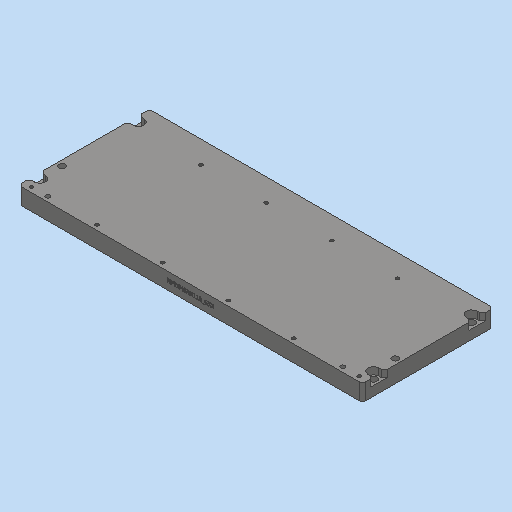
# Autodesk Inventor part: MM0948AN110_G01_100
Saved by Autodesk Inventor 2023.3 (Build 273359000, 359)
## iProperties
Part Number: MM0948AN110_G01_100
Material: 1.2099 X5CrS12
Description: =<RBPARTNOTITLE2>
Document SubType Name: Modeling
Designer: Benutzer
Mass: 35205.2 g
Surface Area: 3659.45 cm^2
Volume: 4484.74 cm^3
Density: 7.85 g/cm^3
Appearance: Stahl - rostfrei AnP
Created: 2023-03-23
RBDOCUMENTTYPE: DRF
RBDOCUMENTVERSION: 00
RBDRAWINGMAINSCALE: 1:1
RBDRAWINGMISSINGSPEC: --
RBDRAWINGVOLUME: --
RBGBEDGESIN1: +0,5
RBGBEDGESIN2: +0,2
RBGBEDGESOUT1: -0,3
RBGBEDGESOUT2: -0,1
RBMATERIAL: =<Material>
RBMATMEETS: --
RBMATNO: =<Part Number>
RBPARTMADEOF: 30 x 240 x 630 (FM)
RBPARTNO: SIEHE MNR
RBPARTNOTITLE1: manufactured part
RBPARTNOTITLE2: Anfertigungsteil
RBPARTSAFETYINDICATOR: --
RBSURFACE: --
RBSURFACE2: --
RBZEDGESNORM: ISO13715:2002-06
RBZGENDIMCLASS: m
RBZGENDIMNORM: ISO 2768-1:1989-11
RBZGENGEOCLASS: H
RBZGENGEONORM: ISO 2768-2:1989-11
RBZSURFACENORM: ISO13D2:2002-02
RBZTOLERANCENORM: ISO 14405-1:2010-12
AnP_Material: =<Material>
AnP_TemplVers: 20190222
AnP_Kategorie: 1
MaxAbmaße: 30 x 240 x 630 (FM)
AnP_Kommentar_aktuell: =<Comments>
AnP_Material_aktuell: =<Material>
Author: FH/Wi
Keywords: =<RBPARTMADEOF>
Comments: =<RBSURFACE2>
Revision Number: 01
Autodesk Inventor part; units mm, degrees
ref_plane "YZ Plane" through (0, 0, 0) normal (1, 0, 0) x (0, 1, 0)
ref_plane "XZ Plane" through (0, 0, 0) normal (0, 1, 0) x (-1, 0, 0)
ref_plane "XY Plane" through (0, 0, 0) normal (0, 0, 1) x (1, 0, 0)
sketch "Skizze1" plane through (0, 0, 0) normal (0, 0, 1) x (1, 0, 0)
  line L0 (-315, 240) -> (315, 240)
  line L1 (315, 240) -> (315, 0)
  line L2 (315, 0) -> (-315, 0)
  line L3 (-315, 0) -> (-315, 240)
  point P0 (0, 0)
  point P1 (0, 0)
  dimension "d0" = 240
  dimension "d1" = 630
  constraints: 8 end point, 2 parallel, 1 coincident, 1 horizontal, 1 midpoint, 1 perpendicular
  measures "d0" distance of L2.end L0.start
  measures "d1" distance of L0.start L0.end
extrude "Extrusion1" add sketch "Skizze1" along normal blind 30
sketch "Skizze2" plane through (0, 0, 30) normal (0, 0, 1) x (1, 0, 0)
  line L0 (-305, 210) -> (305, 210) construction
  line L1 (305, 210) -> (305, 30) construction
  line L2 (305, 30) -> (-305, 30) construction
  line L3 (-305, 30) -> (-305, 210) construction
  line L4 (315, 240) -> (-315, 240) construction
  line L5 (-315, 0) -> (315, 0) construction
  line L6 (-305, -150) -> (305, -150) construction
  line L7 (305, -150) -> (305, -330) construction
  line L8 (305, -330) -> (-305, -330) construction
  line L9 (-305, -330) -> (-305, -150) construction
  point P0 (0, 0)
  point P1 (0, 0)
  point P2 (0, 30)
  dimension "d4" = 610
  dimension "d5" = 30
  dimension "d6" = 180
  dimension "d19" = 180
  dimension "d20" = 180
  constraints: 16 end point, 8 coincident, 4 parallel, 3 vertical alignment, 2 horizontal, 2 midpoint, 2 perpendicular
  measures "d4" distance of L0.start L0.end
  measures "d5" distance between parallel lines of L0 L4
  measures "d6" distance of L2.end L0.start
  measures "d19" distance between parallel lines of L2 L6
  measures "d20" distance of L8.end L6.start
hole "Bohrung1" at (-305, 210, 30) at (305, 210, 30) at (-305, 30, 30) at (305, 30, 30) at (-305, -150, 30) at (-305, -330, 30) at (305, -330, 30) at (305, -150, 30) direction (0, 0, -1) diameter 13.5 end through all counterbore diameter 20 counterbore depth 13 clearance for "Inbusschraube ISO 4762  versenkt" size "M12" standard "ISO"
sketch "Skizze3" plane through (0, 0, 30) normal (0, 0, 1) x (1, 0, 0)
  line L0 (315, 240) -> (-315, 240) projected
  line L1 (-315, 240) -> (-315, 210) projected
  circle A0 centre (-305, 210) radius 10 projected
  line L2 (-315, 210) -> (-315, 30) projected
  circle A1 centre (-305, 30) radius 10 projected
  line L3 (-315, 30) -> (-315, 0) projected
  line L4 (-315, 0) -> (315, 0) projected
  line L5 (315, 0) -> (315, 30) projected
  circle A2 centre (305, 30) radius 10 projected
  line L6 (315, 30) -> (315, 210) projected
  circle A3 centre (305, 210) radius 10 projected
  line L7 (315, 210) -> (315, 240) projected
  line L8 (-305, 220) -> (-315, 220)
  line L9 (-315, 220) -> (-315, 200)
  line L10 (-315, 200) -> (-305, 200)
  line L11 (-305, 200) -> (-305, 220)
  line L12 (-305, 40) -> (-315, 40)
  line L13 (-315, 40) -> (-315, 20)
  line L14 (-315, 20) -> (-305, 20)
  line L15 (-305, 20) -> (-305, 40)
  line L16 (305, 40) -> (315, 40)
  line L17 (315, 40) -> (315, 20)
  line L18 (315, 20) -> (305, 20)
  line L19 (305, 20) -> (305, 40)
  line L20 (305, 220) -> (315, 220)
  line L21 (315, 220) -> (315, 200)
  line L22 (315, 200) -> (305, 200)
  line L23 (305, 200) -> (305, 220)
  circle A4 centre (-305, 210) radius 10 projected
  line L24 (315, 30) -> (315, 210) projected
  line L25 (-315, 30) -> (-315, 0) projected
  line L26 (-315, 210) -> (-315, 30) projected
  line L27 (315, 0) -> (315, 240) projected
  point P0 (315, 30)
  point P1 (305, 30)
  constraints: 32 end point, 8 parallel, 5 horizontal, 4 collinear, 4 perpendicular, 4 point on circle, 4 tangent, 3 point on line, 1 horizontal alignment
extrude "Extrusion2" cut sketch "Skizze3" against normal up to surface (13 mm away) contours L7 A3 L20 | L8 A0 L1 | A3 L23 | L6 L22 A3 | A0 L11 | A0 L10 L2 | L6 A2 L16 | L12 A1 L2 | A2 L19 | L5 L18 A2 | A1 L15 | A1 L14 L3 picked at (306.4463, 213.0032) picked at (-306.4463, 206.9968) picked at (307.6061, 27.9217) picked at (-307.6061, 27.9217)
chamfer "Fase1" distance 5 angle 45 12 edges at (315, 0, 15) (315, 240, 15) (-315, 0, 15) (-315, 240, 15) (-315, 220, 23.5) (-315, 200, 23.5) (-315, 40, 23.5) (-315, 20, 23.5) (315, 20, 23.5) (315, 40, 23.5) (315, 200, 23.5) (315, 220, 23.5)
sketch "Skizze4" plane through (0, 0, 30) normal (0, 0, 1) x (1, 0, 0)
  circle A0 centre (-305, 210) radius 6.75 projected
  circle A1 centre (305, 210) radius 6.75 projected
  point P0 (0, 0)
  point P1 (-305, 170)
  point P2 (305, 170)
  dimension "d21" = 40
  dimension "d22" = 40
  constraints: 2 vertical alignment
  measures "d21" distance of A0.centre point (-305, 170)
  measures "d22" distance of point (305, 170) A1.centre
hole "Bohrung2" at (-305, 170, 30) at (305, 170, 30) direction (0, 0, -1) diameter 12 end through all
sketch "Skizze8" plane through (0, 0, 30) normal (0, 0, 1) x (1, 0, 0)
  line L0 (310, 240) -> (-310, 240) projected
  line L1 (0, 288) -> (0, -48) projected
  line L2 (-441, 0) -> (441, 0) projected
  point P0 (0, 0)
  point P1 (180, 231)
  point P2 (60, 231)
  point P3 (-60, 231)
  point P4 (-180, 231)
  point P5 (-180, 41)
  point P6 (-60, 41)
  point P7 (60, 41)
  point P8 (180, 41)
  point P9 (300, 231)
  point P10 (-300, 231)
  dimension "d59" = 120
  dimension "d60" = 120
  dimension "d61" = 120
  dimension "d62" = 190
  dimension "d63" = 9
  dimension "d89" = 60
  dimension "d94" = 120
  dimension "d95" = 120
  constraints: 8 horizontal alignment, 4 vertical alignment
  measures "d59" distance of point (60, 41) point (180, 41)
  measures "d60" distance of point (-60, 41) point (60, 41)
  measures "d61" distance of point (-180, 41) point (-60, 41)
  measures "d62" distance of point (180, 231) point (180, 41)
  measures "d63" distance from line of point (180, 231) L0
  measures "d89" distance from line of L1 point (-60, 231)
  measures "d94" distance of point (180, 231) point (300, 231)
  measures "d95" distance of point (-300, 231) point (-180, 231)
hole "Bohrung6" at (180, 231, 30) at (60, 231, 30) at (-60, 231, 30) at (-180, 231, 30) at (-180, 41, 30) at (-60, 41, 30) at (60, 41, 30) at (180, 41, 30) at (300, 231, 30) at (-300, 231, 30) direction (0, 0, -1) diameter 6.647 end through all thread size "M8x1.25" designation "M8" class "6H" standard "ISO Metric profile"
sketch "Skizze9" plane through (0, 0, 30) normal (0, 0, 1) x (1, 0, 0)
  circle A0 centre (180, 231) radius 3.3235 projected
  line L0 (0, 288) -> (0, -48) projected
  point P0 (0, 0)
  point P1 (270, 231)
  point P2 (-270, 231)
  dimension "d71" = 0
  dimension "d72" = 540
  dimension "d90" = 90
  constraints: 1 horizontal alignment
  measures "d71" vertical distance of point (-270, 231) point (270, 231)
  measures "d72" distance of point (-270, 231) point (270, 231)
  measures "d90" distance of point (270, 231) A0.centre
hole "Bohrung7" at (270, 231, 30) at (-270, 231, 30) direction (0, 0, -1) diameter 7.8 end through all counterbore diameter 8 counterbore depth 15
sketch "Skizze11" plane through (-310, 240, 0) normal (0, 1, 0) x (1, 0, 0)
  line L0 (528.1373, -4.1156) -> (91.8627, -4.1156) construction
  line L1 (91.8627, -4.1156) -> (91.8627, -25.8844) construction
  line L2 (91.8627, -25.8844) -> (528.1373, -25.8844) construction
  line L3 (528.1373, -25.8844) -> (528.1373, -4.1156) construction
  line L4 (620, -30) -> (0, -30) projected
  line L5 (620, 0) -> (620, -30) projected
  line L6 (0, 0) -> (620, 0) projected
  line L7 (346.6224, -12.124) -> (347.5527, -12.124)
  line L8 (347.5527, -12.124) -> (347.5527, -18.154)
  line L9 (347.5527, -18.154) -> (349.3793, -14.0527)
  line L10 (349.3793, -14.0527) -> (349.9465, -14.0527)
  line L11 (349.9465, -14.0527) -> (351.7561, -18.154)
  line L12 (351.7561, -18.154) -> (351.7561, -12.124)
  line L13 (351.7561, -12.124) -> (352.624, -12.124)
  line L14 (352.624, -12.124) -> (352.624, -19.124)
  line L15 (352.624, -19.124) -> (351.3533, -19.124)
  line L16 (351.3533, -19.124) -> (349.6062, -15.2269)
  line L17 (349.6062, -15.2269) -> (347.9157, -19.124)
  line L18 (347.9157, -19.124) -> (346.6224, -19.124)
  line L19 (346.6224, -19.124) -> (346.6224, -12.124)
  line L20 (339.2026, -12.124) -> (340.1329, -12.124)
  line L21 (340.1329, -12.124) -> (340.1329, -18.154)
  line L22 (340.1329, -18.154) -> (341.9595, -14.0527)
  line L23 (341.9595, -14.0527) -> (342.5267, -14.0527)
  line L24 (342.5267, -14.0527) -> (344.3363, -18.154)
  line L25 (344.3363, -18.154) -> (344.3363, -12.124)
  line L26 (344.3363, -12.124) -> (345.2042, -12.124)
  line L27 (345.2042, -12.124) -> (345.2042, -19.124)
  line L28 (345.2042, -19.124) -> (343.9335, -19.124)
  line L29 (343.9335, -19.124) -> (342.1864, -15.2269)
  line L30 (342.1864, -15.2269) -> (340.4959, -19.124)
  line L31 (340.4959, -19.124) -> (339.2026, -19.124)
  line L32 (339.2026, -19.124) -> (339.2026, -12.124)
  spline S0 degree 2 poles (333.6264, -15.624) (333.6264, -13.7407) (334.7212, -11.9765) (335.8614, -11.9765) knots 0 0 0 1 2 2 2
  spline S1 degree 2 poles (335.8614, -11.9765) (337.0186, -11.9765) (338.1021, -13.7747) (338.1021, -15.6183) knots 0 0 0 1 2 2 2
  spline S2 degree 2 poles (338.1021, -15.6183) (338.1021, -17.513) (337.0073, -19.2658) (335.8614, -19.2658) knots 0 0 0 1 2 2 2
  spline S3 degree 2 poles (335.8614, -19.2658) (334.7099, -19.2658) (333.6264, -17.4506) (333.6264, -15.624) knots 0 0 0 1 2 2 2
  spline S4 degree 2 poles (334.829, -13.4911) (334.6929, -13.8371) (334.5794, -14.9036) (334.5794, -15.624) knots 0 0 0 1 2 2 2
  spline S5 degree 2 poles (334.5794, -15.624) (334.5794, -16.3444) (334.6929, -17.4052) (334.8347, -17.7626) knots 0 0 0 1 2 2 2
  spline S6 degree 2 poles (334.8347, -17.7626) (334.9765, -18.1199) (335.47, -18.4887) (335.8614, -18.4887) knots 0 0 0 1 2 2 2
  spline S7 degree 2 poles (335.8614, -18.4887) (336.2528, -18.4887) (336.7577, -18.1199) (336.9052, -17.7512) knots 0 0 0 1 2 2 2
  spline S8 degree 2 poles (336.9052, -17.7512) (337.047, -17.3938) (337.1491, -16.3047) (337.1491, -15.6183) knots 0 0 0 1 2 2 2
  spline S9 degree 2 poles (337.1491, -15.6183) (337.1491, -14.8809) (337.0583, -13.8938) (336.9109, -13.5081) knots 0 0 0 1 2 2 2
  spline S10 degree 2 poles (336.9109, -13.5081) (336.7747, -13.1451) (336.2699, -12.7536) (335.8614, -12.7536) knots 0 0 0 1 2 2 2
  spline S11 degree 2 poles (335.8614, -12.7536) (335.4757, -12.7536) (334.9708, -13.1224) (334.829, -13.4911) knots 0 0 0 1 2 2 2
  spline S12 degree 2 poles (332.923, -16.8493) (332.923, -17.3882) (332.5713, -18.2844) (332.265, -18.6078) knots 0 0 0 1 2 2 2
  spline S13 degree 2 poles (332.265, -18.6078) (331.9757, -18.9198) (331.1305, -19.2658) (330.6994, -19.2658) knots 0 0 0 1 2 2 2
  spline S14 degree 2 poles (330.6994, -19.2658) (330.2172, -19.2658) (329.4344, -18.9425) (329.1451, -18.6361) knots 0 0 0 1 2 2 2
  spline S15 degree 2 poles (329.1451, -18.6361) (328.782, -18.2504) (328.3849, -17.0024) (328.3849, -16.0438) knots 0 0 0 1 2 2 2
  spline S16 degree 2 poles (328.3849, -16.0438) (328.3849, -15.1759) (328.7763, -13.6216) (329.1564, -13.1053) knots 0 0 0 1 2 2 2
  spline S17 degree 2 poles (329.1564, -13.1053) (329.5592, -12.5608) (330.6937, -11.9878) (331.5219, -11.9878) knots 0 0 0 1 2 2 2
  spline S18 degree 2 poles (331.5219, -11.9878) (331.7091, -11.9878) (332.1345, -12.0276) (332.316, -12.0843) knots 0 0 0 1 2 2 2
  line L33 (332.316, -12.0843) -> (332.316, -12.9862)
  line L34 (332.316, -12.9862) -> (332.2707, -12.9862)
  spline S19 degree 2 poles (332.2707, -12.9862) (332.1515, -12.9182) (331.6524, -12.799) (331.3971, -12.799) knots 0 0 0 1 2 2 2
  spline S20 degree 2 poles (331.3971, -12.799) (330.4781, -12.799) (329.4287, -14.013) (329.3549, -15.1361) knots 0 0 0 1 2 2 2
  spline S21 degree 2 poles (329.3549, -15.1361) (329.7293, -14.8809) (330.41, -14.6483) (330.8128, -14.6483) knots 0 0 0 1 2 2 2
  spline S22 degree 2 poles (330.8128, -14.6483) (331.1985, -14.6483) (331.8395, -14.8185) (332.1629, -15.0624) knots 0 0 0 1 2 2 2
  spline S23 degree 2 poles (332.1629, -15.0624) (332.5373, -15.3517) (332.923, -16.231) (332.923, -16.8493) knots 0 0 0 1 2 2 2
  spline S24 degree 2 poles (329.3323, -16.2536) (329.3323, -16.9627) (329.5932, -17.859) (329.8258, -18.1029) knots 0 0 0 1 2 2 2
  spline S25 degree 2 poles (329.8258, -18.1029) (330.03, -18.3298) (330.4554, -18.5) (330.705, -18.5) knots 0 0 0 1 2 2 2
  spline S26 degree 2 poles (330.705, -18.5) (331.2836, -18.5) (331.97, -17.6718) (331.97, -16.889) knots 0 0 0 1 2 2 2
  spline S27 degree 2 poles (331.97, -16.889) (331.97, -16.4465) (331.7431, -15.8736) (331.4935, -15.6694) knots 0 0 0 1 2 2 2
  spline S28 degree 2 poles (331.4935, -15.6694) (331.312, -15.5219) (330.8639, -15.4254) (330.6029, -15.4254) knots 0 0 0 1 2 2 2
  spline S29 degree 2 poles (330.6029, -15.4254) (330.3023, -15.4254) (329.6102, -15.6353) (329.3493, -15.8112) knots 0 0 0 1 2 2 2
  spline S30 degree 2 poles (329.3493, -15.8112) (329.3436, -15.8793) (329.3323, -16.1118) (329.3323, -16.2536) knots 0 0 0 1 2 2 2
  line L35 (322.9733, -14.5292) -> (323.8071, -14.5292)
  line L36 (323.8071, -14.5292) -> (323.8071, -12.124)
  line L37 (323.8071, -12.124) -> (324.7091, -12.124)
  line L38 (324.7091, -12.124) -> (324.7091, -14.5292)
  line L39 (324.7091, -14.5292) -> (327.8006, -14.5292)
  line L40 (327.8006, -14.5292) -> (327.8006, -15.5162)
  line L41 (327.8006, -15.5162) -> (324.6694, -19.124)
  line L42 (324.6694, -19.124) -> (323.8071, -19.124)
  line L43 (323.8071, -19.124) -> (323.8071, -15.2836)
  line L44 (323.8071, -15.2836) -> (322.9733, -15.2836)
  line L45 (322.9733, -15.2836) -> (322.9733, -14.5292)
  line L46 (324.7091, -15.2836) -> (324.7091, -18.0178)
  line L47 (324.7091, -18.0178) -> (327.0632, -15.2836)
  line L48 (327.0632, -15.2836) -> (324.7091, -15.2836)
  spline S31 degree 2 poles (320.1086, -11.9652) (320.6305, -11.9652) (321.487, -12.2771) (321.7877, -12.5665) knots 0 0 0 1 2 2 2
  spline S32 degree 2 poles (321.7877, -12.5665) (322.0827, -12.8501) (322.389, -13.6216) (322.389, -14.0583) knots 0 0 0 1 2 2 2
  spline S33 degree 2 poles (322.389, -14.0583) (322.389, -14.6256) (321.782, -15.5786) (321.2034, -15.8622) knots 0 0 0 1 2 2 2
  line L49 (321.2034, -15.8622) -> (321.2034, -15.8906)
  spline S34 degree 2 poles (321.2034, -15.8906) (321.7196, -16.1912) (322.2188, -16.906) (322.2188, -17.4392) knots 0 0 0 1 2 2 2
  spline S35 degree 2 poles (322.2188, -17.4392) (322.2188, -18.2277) (321.0276, -19.2828) (320.1086, -19.2828) knots 0 0 0 1 2 2 2
  spline S36 degree 2 poles (320.1086, -19.2828) (319.1556, -19.2828) (318.0041, -18.2844) (318.0041, -17.5016) knots 0 0 0 1 2 2 2
  spline S37 degree 2 poles (318.0041, -17.5016) (318.0041, -17.0308) (318.5543, -16.1118) (319.0705, -15.8509) knots 0 0 0 1 2 2 2
  line L50 (319.0705, -15.8509) -> (319.0705, -15.8225)
  spline S38 degree 2 poles (319.0705, -15.8225) (318.4579, -15.5389) (317.8282, -14.722) (317.8282, -14.0754) knots 0 0 0 1 2 2 2
  spline S39 degree 2 poles (317.8282, -14.0754) (317.8282, -13.1791) (319.1329, -11.9652) (320.1086, -11.9652) knots 0 0 0 1 2 2 2
  spline S40 degree 2 poles (318.7925, -13.9846) (318.7925, -14.4157) (319.1329, -14.9263) (319.6151, -15.1872) knots 0 0 0 1 2 2 2
  spline S41 degree 2 poles (319.6151, -15.1872) (319.7739, -15.278) (320.3071, -15.4878) (320.6418, -15.624) knots 0 0 0 1 2 2 2
  spline S42 degree 2 poles (320.6418, -15.624) (321.0276, -15.3687) (321.4417, -14.6086) (321.4417, -14.1264) knots 0 0 0 1 2 2 2
  spline S43 degree 2 poles (321.4417, -14.1264) (321.4417, -13.4911) (320.6759, -12.6629) (320.0972, -12.6629) knots 0 0 0 1 2 2 2
  spline S44 degree 2 poles (320.0972, -12.6629) (319.5073, -12.6629) (318.7925, -13.372) (318.7925, -13.9846) knots 0 0 0 1 2 2 2
  spline S45 degree 2 poles (318.923, -17.4903) (318.923, -17.9611) (319.5527, -18.5908) (320.1143, -18.5908) knots 0 0 0 1 2 2 2
  spline S46 degree 2 poles (320.1143, -18.5908) (320.6248, -18.5908) (321.2771, -18.0292) (321.2771, -17.547) knots 0 0 0 1 2 2 2
  spline S47 degree 2 poles (321.2771, -17.547) (321.2771, -17.201) (320.9425, -16.7188) (320.6078, -16.5259) knots 0 0 0 1 2 2 2
  spline S48 degree 2 poles (320.6078, -16.5259) (320.466, -16.4465) (319.8647, -16.1686) (319.6207, -16.0891) knots 0 0 0 1 2 2 2
  spline S49 degree 2 poles (319.6207, -16.0891) (319.2123, -16.4011) (318.923, -17.0648) (318.923, -17.4903) knots 0 0 0 1 2 2 2
  line L51 (317.5276, -12.124) -> (315.1677, -19.124)
  line L52 (315.1677, -19.124) -> (314.0219, -19.124)
  line L53 (314.0219, -19.124) -> (311.6621, -12.124)
  line L54 (311.6621, -12.124) -> (312.6434, -12.124)
  line L55 (312.6434, -12.124) -> (313.2788, -14.081)
  line L56 (313.2788, -14.081) -> (315.9506, -14.081)
  line L57 (315.9506, -14.081) -> (316.5859, -12.124)
  line L58 (316.5859, -12.124) -> (317.5276, -12.124)
  line L59 (313.534, -14.8752) -> (314.6175, -18.171)
  line L60 (314.6175, -18.171) -> (315.6953, -14.8752)
  line L61 (315.6953, -14.8752) -> (313.534, -14.8752)
  line L62 (305.9895, -12.124) -> (307.0332, -12.124)
  line L63 (307.0332, -12.124) -> (310.1305, -18.1596)
  line L64 (310.1305, -18.1596) -> (310.1305, -12.124)
  line L65 (310.1305, -12.124) -> (310.9984, -12.124)
  line L66 (310.9984, -12.124) -> (310.9984, -19.124)
  line L67 (310.9984, -19.124) -> (309.6767, -19.124)
  line L68 (309.6767, -19.124) -> (306.8574, -13.5818)
  line L69 (306.8574, -13.5818) -> (306.8574, -19.124)
  line L70 (306.8574, -19.124) -> (305.9895, -19.124)
  line L71 (305.9895, -19.124) -> (305.9895, -12.124)
  line L72 (300.8047, -12.124) -> (304.2196, -12.124)
  line L73 (304.2196, -12.124) -> (304.2196, -12.8387)
  line L74 (304.2196, -12.8387) -> (302.9489, -12.8387)
  line L75 (302.9489, -12.8387) -> (302.9489, -17.53)
  line L76 (302.9489, -17.53) -> (304.2196, -17.53)
  line L77 (304.2196, -17.53) -> (304.2196, -18.171)
  spline S50 degree 2 poles (304.2196, -18.171) (303.4992, -18.171) (302.8185, -18.5794) (302.7731, -19.1467) knots 0 0 0 1 2 2 2
  line L78 (302.7731, -19.1467) -> (302.047, -19.1467)
  line L79 (302.047, -19.1467) -> (302.047, -12.8387)
  line L80 (302.047, -12.8387) -> (300.8047, -12.8387)
  line L81 (300.8047, -12.8387) -> (300.8047, -12.124)
  line L82 (295.5519, -12.124) -> (298.9668, -12.124)
  line L83 (298.9668, -12.124) -> (298.9668, -12.8387)
  line L84 (298.9668, -12.8387) -> (297.6961, -12.8387)
  line L85 (297.6961, -12.8387) -> (297.6961, -17.53)
  line L86 (297.6961, -17.53) -> (298.9668, -17.53)
  line L87 (298.9668, -17.53) -> (298.9668, -18.171)
  spline S51 degree 2 poles (298.9668, -18.171) (298.2464, -18.171) (297.5656, -18.5794) (297.5203, -19.1467) knots 0 0 0 1 2 2 2
  line L88 (297.5203, -19.1467) -> (296.7942, -19.1467)
  line L89 (296.7942, -19.1467) -> (296.7942, -12.8387)
  line L90 (296.7942, -12.8387) -> (295.5519, -12.8387)
  line L91 (295.5519, -12.8387) -> (295.5519, -12.124)
  spline S52 degree 2 poles (289.9076, -15.624) (289.9076, -13.7407) (291.0024, -11.9765) (292.1426, -11.9765) knots 0 0 0 1 2 2 2
  spline S53 degree 2 poles (292.1426, -11.9765) (293.2998, -11.9765) (294.3833, -13.7747) (294.3833, -15.6183) knots 0 0 0 1 2 2 2
  spline S54 degree 2 poles (294.3833, -15.6183) (294.3833, -17.513) (293.2885, -19.2658) (292.1426, -19.2658) knots 0 0 0 1 2 2 2
  spline S55 degree 2 poles (292.1426, -19.2658) (290.9911, -19.2658) (289.9076, -17.4506) (289.9076, -15.624) knots 0 0 0 1 2 2 2
  spline S56 degree 2 poles (291.1102, -13.4911) (290.9741, -13.8371) (290.8606, -14.9036) (290.8606, -15.624) knots 0 0 0 1 2 2 2
  spline S57 degree 2 poles (290.8606, -15.624) (290.8606, -16.3444) (290.9741, -17.4052) (291.1159, -17.7626) knots 0 0 0 1 2 2 2
  spline S58 degree 2 poles (291.1159, -17.7626) (291.2577, -18.1199) (291.7512, -18.4887) (292.1426, -18.4887) knots 0 0 0 1 2 2 2
  spline S59 degree 2 poles (292.1426, -18.4887) (292.534, -18.4887) (293.0389, -18.1199) (293.1864, -17.7512) knots 0 0 0 1 2 2 2
  spline S60 degree 2 poles (293.1864, -17.7512) (293.3282, -17.3938) (293.4303, -16.3047) (293.4303, -15.6183) knots 0 0 0 1 2 2 2
  spline S61 degree 2 poles (293.4303, -15.6183) (293.4303, -14.8809) (293.3395, -13.8938) (293.1921, -13.5081) knots 0 0 0 1 2 2 2
  spline S62 degree 2 poles (293.1921, -13.5081) (293.0559, -13.1451) (292.5511, -12.7536) (292.1426, -12.7536) knots 0 0 0 1 2 2 2
  spline S63 degree 2 poles (292.1426, -12.7536) (291.7569, -12.7536) (291.252, -13.1224) (291.1102, -13.4911) knots 0 0 0 1 2 2 2
  line L92 (284.1953, -10.7172) -> (289.5956, -10.7172)
  line L93 (289.5956, -10.7172) -> (289.5956, -11.3241)
  line L94 (289.5956, -11.3241) -> (284.1953, -11.3241)
  line L95 (284.1953, -11.3241) -> (284.1953, -10.7172)
  spline S64 degree 2 poles (280.6272, -11.9878) (281.3703, -11.9878) (282.6013, -12.4417) (283.0438, -12.9011) knots 0 0 0 1 2 2 2
  spline S65 degree 2 poles (283.0438, -12.9011) (283.4862, -13.3663) (283.9571, -14.7391) (283.9571, -15.6297) knots 0 0 0 1 2 2 2
  spline S66 degree 2 poles (283.9571, -15.6297) (283.9571, -16.4749) (283.4806, -17.8136) (283.0381, -18.2901) knots 0 0 0 1 2 2 2
  spline S67 degree 2 poles (283.0381, -18.2901) (282.6126, -18.7496) (281.3647, -19.2488) (280.6216, -19.2488) knots 0 0 0 1 2 2 2
  spline S68 degree 2 poles (280.6216, -19.2488) (280.2642, -19.2488) (279.6175, -19.1467) (279.3225, -19.0559) knots 0 0 0 1 2 2 2
  spline S69 degree 2 poles (279.3225, -19.0559) (279.0843, -18.9878) (278.5057, -18.7382) (278.3298, -18.6475) knots 0 0 0 1 2 2 2
  line L96 (278.3298, -18.6475) -> (278.3298, -17.5243)
  line L97 (278.3298, -17.5243) -> (278.4092, -17.5243)
  spline S70 degree 2 poles (278.4092, -17.5243) (278.5851, -17.6775) (278.9538, -17.9554) (279.2942, -18.1143) knots 0 0 0 1 2 2 2
  spline S71 degree 2 poles (279.2942, -18.1143) (279.5778, -18.2561) (280.3096, -18.4433) (280.7293, -18.4433) knots 0 0 0 1 2 2 2
  spline S72 degree 2 poles (280.7293, -18.4433) (281.7391, -18.4433) (282.987, -16.923) (282.987, -15.658) knots 0 0 0 1 2 2 2
  spline S73 degree 2 poles (282.987, -15.658) (282.987, -14.9546) (282.658, -13.8995) (282.346, -13.5365) knots 0 0 0 1 2 2 2
  spline S74 degree 2 poles (282.346, -13.5365) (282.0454, -13.1734) (281.1945, -12.7934) (280.6613, -12.7934) knots 0 0 0 1 2 2 2
  spline S75 degree 2 poles (280.6613, -12.7934) (280.2699, -12.7934) (279.487, -12.9068) (279.2204, -13.0203) knots 0 0 0 1 2 2 2
  line L98 (279.2204, -13.0203) -> (279.2204, -14.8298)
  line L99 (279.2204, -14.8298) -> (280.8428, -14.8298)
  line L100 (280.8428, -14.8298) -> (280.8428, -15.6467)
  line L101 (280.8428, -15.6467) -> (278.3015, -15.6467)
  line L102 (278.3015, -15.6467) -> (278.3015, -12.5891)
  spline S76 degree 2 poles (278.3015, -12.5891) (278.4773, -12.5097) (279.0786, -12.2658) (279.3339, -12.1921) knots 0 0 0 1 2 2 2
  spline S77 degree 2 poles (279.3339, -12.1921) (279.6799, -12.09) (280.2358, -11.9878) (280.6272, -11.9878) knots 0 0 0 1 2 2 2
  line L103 (272.2942, -12.124) -> (273.3606, -12.124)
  line L104 (273.3606, -12.124) -> (275.0624, -14.9149)
  line L105 (275.0624, -14.9149) -> (276.7982, -12.124)
  line L106 (276.7982, -12.124) -> (277.8023, -12.124)
  line L107 (277.8023, -12.124) -> (275.5729, -15.6297)
  line L108 (275.5729, -15.6297) -> (277.7342, -19.124)
  line L109 (277.7342, -19.124) -> (276.6677, -19.124)
  line L110 (276.6677, -19.124) -> (275, -16.3841)
  line L111 (275, -16.3841) -> (273.2982, -19.124)
  line L112 (273.2982, -19.124) -> (272.2942, -19.124)
  line L113 (272.2942, -19.124) -> (274.4838, -15.675)
  line L114 (274.4838, -15.675) -> (272.2942, -12.124)
  line L115 (266.7066, -12.124) -> (267.7731, -12.124)
  line L116 (267.7731, -12.124) -> (269.4749, -14.9149)
  line L117 (269.4749, -14.9149) -> (271.2107, -12.124)
  line L118 (271.2107, -12.124) -> (272.2148, -12.124)
  line L119 (272.2148, -12.124) -> (269.9854, -15.6297)
  line L120 (269.9854, -15.6297) -> (272.1467, -19.124)
  line L121 (272.1467, -19.124) -> (271.0802, -19.124)
  line L122 (271.0802, -19.124) -> (269.4125, -16.3841)
  line L123 (269.4125, -16.3841) -> (267.7107, -19.124)
  line L124 (267.7107, -19.124) -> (266.7066, -19.124)
  line L125 (266.7066, -19.124) -> (268.8963, -15.675)
  line L126 (268.8963, -15.675) -> (266.7066, -12.124)
  point P0 (310, 0)
  point P1 (528.1373, -15)
  point P2 (620, -15)
  point P3 (310, -4.1156)
  point P4 (310, 0)
  constraints: 4 midpoint, 1 horizontal alignment, 1 vertical alignment, 2 other
emboss "Prägen1" sketch "Skizze11" operation cut depth 0.1 direction (0, -1, 0)
equation "\"d60\" = d59"
equation "\"d61\" = d59"
